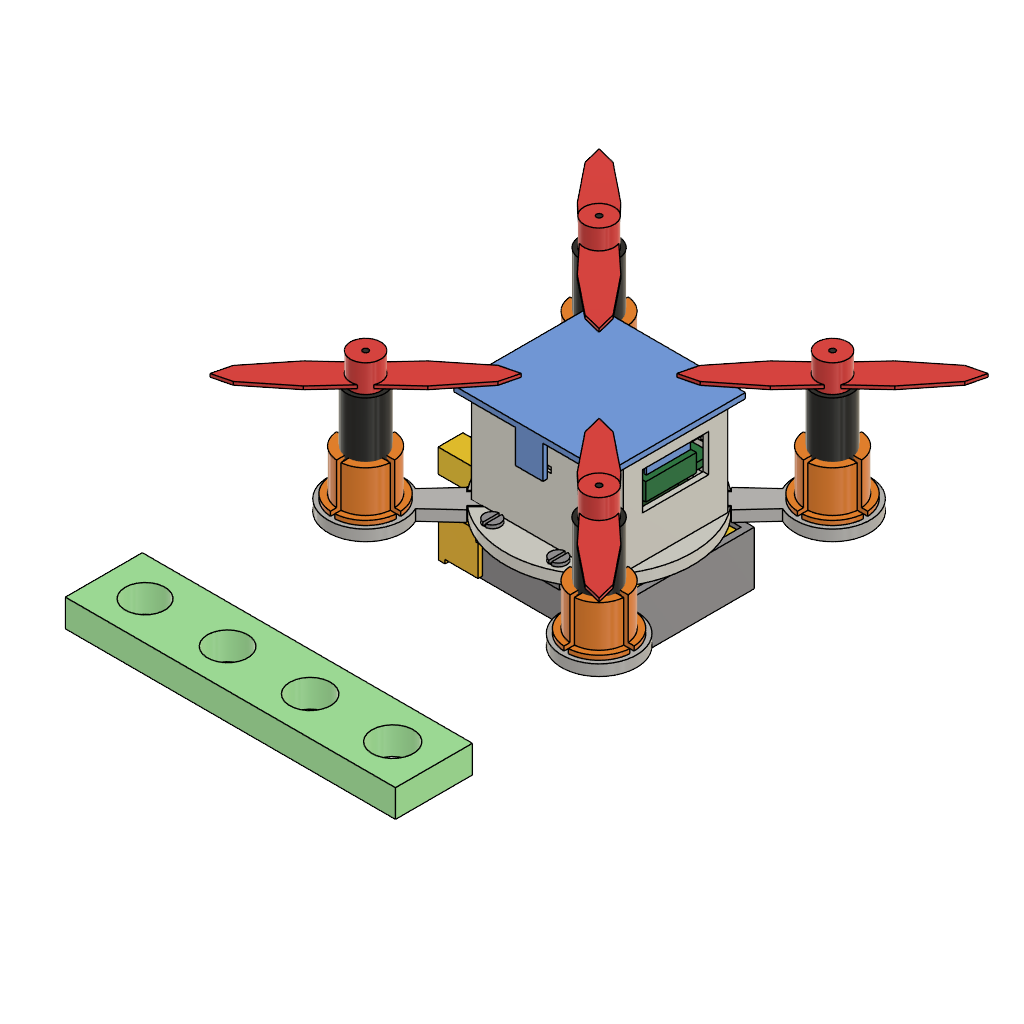
MINI DRONE S3 (Autodesk Fusion 360 design; units mm, degrees)
part number: 2026-10-19-23-11-20-480
part number: 2026-10-19-23-11-20-874
part number: 2026-10-19-23-11-22-508
part number: 2026-10-19-23-11-23-026
part number: 2026-10-19-23-11-23-873
part number: 2026-10-19-23-11-24-034
part number: 2026-10-19-23-11-24-322
part number: 2026-10-19-23-11-25-069
part number: 2026-10-19-23-11-26-284
part number: 2026-10-19-23-11-26-518
part number: 2026-10-19-23-11-26-952
part number: 2026-10-19-23-11-28-014
part number: 2026-10-19-23-11-29-690
part number: 2026-10-19-23-11-29-984
part number: 2026-10-19-23-11-30-548
part number: 2026-10-19-23-11-31-840
part number: 2026-10-19-23-11-33-880
part number: 2026-10-19-23-11-34-265
part number: 2026-10-19-23-11-35-210
part number: 2026-10-19-23-11-38-484
part number: 2026-10-19-23-11-46-425
part number: 2026-10-19-23-11-48-847
part number: 2026-10-19-23-11-50-722
part number: 2026-10-19-23-11-52-088
part number: 2026-10-19-23-11-53-497
part number: 2026-10-19-23-11-56-236
Autodesk Fusion 360 part; units mm, degrees
(part 1 of 2)
sketch "Sketch1" plane through (0, 0, 0) normal (0, 0, 1) x (1, 0, 0) in component "Frame_Core"
  circle A0 centre (0, 0) radius 17
extrude "Extrude1" add sketch "Sketch1" along normal blind 2 makes body 1 in component "Frame_Core"
sketch "Sketch2" plane through (0, 0, 0) normal (0, 0, 1) x (1, 0, 0) in component "Frame_Core"
  line L0 (6.7175, 2.4749) -> (8.8388, 4.5962)
  line L1 (8.8388, 4.5962) -> (4.5962, 8.8388)
  line L2 (4.5962, 8.8388) -> (2.4749, 6.7175)
  line L3 (2.4749, 6.7175) -> (6.7175, 2.4749)
extrude "Extrude2" cut sketch "Sketch2" along normal blind 2.2 from surface at -0.1 bodies 1 in component "Frame_Core"
sketch "Sketch3" plane through (0, 0, 0) normal (0, 0, 1) x (1, 0, 0) in component "Frame_Core"
  line L0 (7.9196, 5.374) -> (14.1421, 11.5966)
  line L1 (14.1421, 11.5966) -> (11.5966, 14.1421)
  line L2 (11.5966, 14.1421) -> (5.374, 7.9196)
  line L3 (5.374, 7.9196) -> (7.9196, 5.374)
extrude "Extrude3" cut sketch "Sketch3" along normal blind 2.2 from surface at -0.1 bodies 1 in component "Frame_Core"
sketch "Sketch4" plane through (0, 0, 0) normal (0, 0, 1) x (1, 0, 0) in component "Frame_Core"
  line L0 (-2.4749, 6.7175) -> (-4.5962, 8.8388)
  line L1 (-4.5962, 8.8388) -> (-8.8388, 4.5962)
  line L2 (-8.8388, 4.5962) -> (-6.7175, 2.4749)
  line L3 (-6.7175, 2.4749) -> (-2.4749, 6.7175)
extrude "Extrude4" cut sketch "Sketch4" along normal blind 2.2 from surface at -0.1 bodies 1 in component "Frame_Core"
sketch "Sketch5" plane through (0, 0, 0) normal (0, 0, 1) x (1, 0, 0) in component "Frame_Core"
  line L0 (-5.374, 7.9196) -> (-11.5966, 14.1421)
  line L1 (-11.5966, 14.1421) -> (-14.1421, 11.5966)
  line L2 (-14.1421, 11.5966) -> (-7.9196, 5.374)
  line L3 (-7.9196, 5.374) -> (-5.374, 7.9196)
extrude "Extrude5" cut sketch "Sketch5" along normal blind 2.2 from surface at -0.1 bodies 1 in component "Frame_Core"
sketch "Sketch6" plane through (0, 0, 0) normal (0, 0, 1) x (1, 0, 0) in component "Frame_Core"
  line L0 (-6.7175, -2.4749) -> (-8.8388, -4.5962)
  line L1 (-8.8388, -4.5962) -> (-4.5962, -8.8388)
  line L2 (-4.5962, -8.8388) -> (-2.4749, -6.7175)
  line L3 (-2.4749, -6.7175) -> (-6.7175, -2.4749)
extrude "Extrude6" cut sketch "Sketch6" along normal blind 2.2 from surface at -0.1 bodies 1 in component "Frame_Core"
sketch "Sketch7" plane through (0, 0, 0) normal (0, 0, 1) x (1, 0, 0) in component "Frame_Core"
  line L0 (-7.9196, -5.374) -> (-14.1421, -11.5966)
  line L1 (-14.1421, -11.5966) -> (-11.5966, -14.1421)
  line L2 (-11.5966, -14.1421) -> (-5.374, -7.9196)
  line L3 (-5.374, -7.9196) -> (-7.9196, -5.374)
extrude "Extrude7" cut sketch "Sketch7" along normal blind 2.2 from surface at -0.1 bodies 1 in component "Frame_Core"
sketch "Sketch8" plane through (0, 0, 0) normal (0, 0, 1) x (1, 0, 0) in component "Frame_Core"
  line L0 (2.4749, -6.7175) -> (4.5962, -8.8388)
  line L1 (4.5962, -8.8388) -> (8.8388, -4.5962)
  line L2 (8.8388, -4.5962) -> (6.7175, -2.4749)
  line L3 (6.7175, -2.4749) -> (2.4749, -6.7175)
extrude "Extrude8" cut sketch "Sketch8" along normal blind 2.2 from surface at -0.1 bodies 1 in component "Frame_Core"
sketch "Sketch9" plane through (0, 0, 0) normal (0, 0, 1) x (1, 0, 0) in component "Frame_Core"
  line L0 (5.374, -7.9196) -> (11.5966, -14.1421)
  line L1 (11.5966, -14.1421) -> (14.1421, -11.5966)
  line L2 (14.1421, -11.5966) -> (7.9196, -5.374)
  line L3 (7.9196, -5.374) -> (5.374, -7.9196)
extrude "Extrude9" cut sketch "Sketch9" along normal blind 2.2 from surface at -0.1 bodies 1 in component "Frame_Core"
sketch "Sketch10" plane through (0, 0, 0) normal (0, 0, 1) x (1, 0, 0) in component "Frame_Core"
  circle A0 centre (-6, -13.4) radius 1.4
extrude "Extrude10" cut sketch "Sketch10" along normal blind 2.2 from surface at -0.1 bodies 1 in component "Frame_Core"
sketch "Sketch11" plane through (0, 0, 0) normal (0, 0, 1) x (1, 0, 0) in component "Frame_Core"
  circle A0 centre (-6, 13.4) radius 1.4
extrude "Extrude11" cut sketch "Sketch11" along normal blind 2.2 from surface at -0.1 bodies 1 in component "Frame_Core"
sketch "Sketch12" plane through (0, 0, 0) normal (0, 0, 1) x (1, 0, 0) in component "Frame_Core"
  circle A0 centre (6, -13.4) radius 1.4
extrude "Extrude12" cut sketch "Sketch12" along normal blind 2.2 from surface at -0.1 bodies 1 in component "Frame_Core"
sketch "Sketch13" plane through (0, 0, 0) normal (0, 0, 1) x (1, 0, 0) in component "Frame_Core"
  circle A0 centre (6, 13.4) radius 1.4
extrude "Extrude13" cut sketch "Sketch13" along normal blind 2.2 from surface at -0.1 bodies 1 in component "Frame_Core"
sketch "Sketch14" plane through (0, 0, 0) normal (0, 0, 1) x (1, 0, 0) in component "Frame_Core"
  line L0 (-11.5, -11.7) -> (11.5, -11.7)
  line L1 (11.5, -11.7) -> (11.5, -9.5)
  line L2 (11.5, -9.5) -> (-11.5, -9.5)
  line L3 (-11.5, -9.5) -> (-11.5, -11.7)
extrude "Extrude14" add sketch "Sketch14" along normal blind 16.4 from surface at 1.9 bodies 1 in component "Frame_Core"
sketch "Sketch15" plane through (0, 0, 0) normal (0, 0, 1) x (1, 0, 0) in component "Frame_Core"
  line L0 (-11.5, 9.5) -> (11.5, 9.5)
  line L1 (11.5, 9.5) -> (11.5, 11.7)
  line L2 (11.5, 11.7) -> (-11.5, 11.7)
  line L3 (-11.5, 11.7) -> (-11.5, 9.5)
extrude "Extrude15" add sketch "Sketch15" along normal blind 16.4 from surface at 1.9 bodies 1 in component "Frame_Core"
sketch "Sketch16" plane through (0, 0, 0) normal (0, 0, 1) x (1, 0, 0) in component "Frame_Core"
  line L0 (12.9, -9.5) -> (13.9, -9.5)
  line L1 (13.9, -9.5) -> (13.9, 9.5)
  line L2 (13.9, 9.5) -> (12.9, 9.5)
  line L3 (12.9, 9.5) -> (12.9, -9.5)
extrude "Extrude16" add sketch "Sketch16" along normal blind 16.4 from surface at 1.9 bodies 1 in component "Frame_Core"
sketch "Sketch17" plane through (0, 0, 0) normal (0, 0, 1) x (1, 0, 0) in component "Frame_Core"
  line L0 (-11.5, -9.6) -> (11.5, -9.6)
  line L1 (11.5, -9.6) -> (11.5, -8)
  line L2 (11.5, -8) -> (-11.5, -8)
  line L3 (-11.5, -8) -> (-11.5, -9.6)
extrude "Extrude17" add sketch "Sketch17" along normal blind 1.3 from surface at 1.9 bodies 1 in component "Frame_Core"
sketch "Sketch18" plane through (0, 0, 0) normal (0, 0, 1) x (1, 0, 0) in component "Frame_Core"
  line L0 (-11.5, -9.6) -> (11.5, -9.6)
  line L1 (11.5, -9.6) -> (11.5, -8)
  line L2 (11.5, -8) -> (-11.5, -8)
  line L3 (-11.5, -8) -> (-11.5, -9.6)
extrude "Extrude18" add sketch "Sketch18" along normal blind 1 from surface at 5.1 bodies 1 in component "Frame_Core"
sketch "Sketch19" plane through (0, 0, 0) normal (0, 0, 1) x (1, 0, 0) in component "Frame_Core"
  line L0 (-11.5, 8) -> (11.5, 8)
  line L1 (11.5, 8) -> (11.5, 9.6)
  line L2 (11.5, 9.6) -> (-11.5, 9.6)
  line L3 (-11.5, 9.6) -> (-11.5, 8)
extrude "Extrude19" add sketch "Sketch19" along normal blind 1.3 from surface at 1.9 bodies 1 in component "Frame_Core"
sketch "Sketch20" plane through (0, 0, 0) normal (0, 0, 1) x (1, 0, 0) in component "Frame_Core"
  line L0 (-11.5, 8) -> (11.5, 8)
  line L1 (11.5, 8) -> (11.5, 9.6)
  line L2 (11.5, 9.6) -> (-11.5, 9.6)
  line L3 (-11.5, 9.6) -> (-11.5, 8)
extrude "Extrude20" add sketch "Sketch20" along normal blind 1 from surface at 5.1 bodies 1 in component "Frame_Core"
sketch "Sketch21" plane through (0, 0, 0) normal (0, 0, 1) x (1, 0, 0) in component "Frame_Core"
  line L0 (-11.5, -9.6) -> (11.5, -9.6)
  line L1 (11.5, -9.6) -> (11.5, -7.9)
  line L2 (11.5, -7.9) -> (-11.5, -7.9)
  line L3 (-11.5, -7.9) -> (-11.5, -9.6)
extrude "Extrude21" add sketch "Sketch21" along normal blind 1.1 from surface at 8.9 bodies 1 in component "Frame_Core"
sketch "Sketch22" plane through (0, 0, 0) normal (0, 0, 1) x (1, 0, 0) in component "Frame_Core"
  line L0 (-11.5, -9.6) -> (11.5, -9.6)
  line L1 (11.5, -9.6) -> (11.5, -7.9)
  line L2 (11.5, -7.9) -> (-11.5, -7.9)
  line L3 (-11.5, -7.9) -> (-11.5, -9.6)
extrude "Extrude22" add sketch "Sketch22" along normal blind 1 from surface at 11.5 bodies 1 in component "Frame_Core"
sketch "Sketch23" plane through (0, 0, 0) normal (0, 0, 1) x (1, 0, 0) in component "Frame_Core"
  line L0 (-11.5, 7.9) -> (11.5, 7.9)
  line L1 (11.5, 7.9) -> (11.5, 9.6)
  line L2 (11.5, 9.6) -> (-11.5, 9.6)
  line L3 (-11.5, 9.6) -> (-11.5, 7.9)
extrude "Extrude23" add sketch "Sketch23" along normal blind 1.1 from surface at 8.9 bodies 1 in component "Frame_Core"
sketch "Sketch24" plane through (0, 0, 0) normal (0, 0, 1) x (1, 0, 0) in component "Frame_Core"
  line L0 (-11.5, 7.9) -> (11.5, 7.9)
  line L1 (11.5, 7.9) -> (11.5, 9.6)
  line L2 (11.5, 9.6) -> (-11.5, 9.6)
  line L3 (-11.5, 9.6) -> (-11.5, 7.9)
extrude "Extrude24" add sketch "Sketch24" along normal blind 1 from surface at 11.5 bodies 1 in component "Frame_Core"
sketch "Sketch25" plane through (0, 0, 0) normal (0, 0, 1) x (1, 0, 0) in component "Frame_Core"
  line L0 (-11.5, -9.6) -> (11.5, -9.6)
  line L1 (11.5, -9.6) -> (11.5, -7)
  line L2 (11.5, -7) -> (-11.5, -7)
  line L3 (-11.5, -7) -> (-11.5, -9.6)
extrude "Extrude25" add sketch "Sketch25" along normal blind 1.1 from surface at 13.4 bodies 1 in component "Frame_Core"
sketch "Sketch26" plane through (0, 0, 0) normal (0, 0, 1) x (1, 0, 0) in component "Frame_Core"
  line L0 (-11.5, -9.6) -> (11.5, -9.6)
  line L1 (11.5, -9.6) -> (11.5, -7)
  line L2 (11.5, -7) -> (-11.5, -7)
  line L3 (-11.5, -7) -> (-11.5, -9.6)
extrude "Extrude26" add sketch "Sketch26" along normal blind 1 from surface at 16.4 bodies 1 in component "Frame_Core"
sketch "Sketch27" plane through (0, 0, 0) normal (0, 0, 1) x (1, 0, 0) in component "Frame_Core"
  line L0 (-11.5, 7) -> (11.5, 7)
  line L1 (11.5, 7) -> (11.5, 9.6)
  line L2 (11.5, 9.6) -> (-11.5, 9.6)
  line L3 (-11.5, 9.6) -> (-11.5, 7)
extrude "Extrude27" add sketch "Sketch27" along normal blind 1.1 from surface at 13.4 bodies 1 in component "Frame_Core"
sketch "Sketch28" plane through (0, 0, 0) normal (0, 0, 1) x (1, 0, 0) in component "Frame_Core"
  line L0 (-11.5, 7) -> (11.5, 7)
  line L1 (11.5, 7) -> (11.5, 9.6)
  line L2 (11.5, 9.6) -> (-11.5, 9.6)
  line L3 (-11.5, 9.6) -> (-11.5, 7)
extrude "Extrude28" add sketch "Sketch28" along normal blind 1 from surface at 16.4 bodies 1 in component "Frame_Core"
sketch "Sketch29" plane through (0, 0, 0) normal (0, 0, 1) x (1, 0, 0) in component "Frame_Core"
  line L0 (-3, -11.8) -> (3, -11.8)
  line L1 (3, -11.8) -> (3, -11.2)
  line L2 (3, -11.2) -> (-3, -11.2)
  line L3 (-3, -11.2) -> (-3, -11.8)
extrude "Extrude29" cut sketch "Sketch29" along normal blind 1 from surface at 13.3 bodies 1 in component "Frame_Core"
sketch "Sketch30" plane through (0, 0, 0) normal (0, 0, 1) x (1, 0, 0) in component "Frame_Core"
  line L0 (-3, 11.2) -> (3, 11.2)
  line L1 (3, 11.2) -> (3, 11.8)
  line L2 (3, 11.8) -> (-3, 11.8)
  line L3 (-3, 11.8) -> (-3, 11.2)
extrude "Extrude30" cut sketch "Sketch30" along normal blind 1 from surface at 13.3 bodies 1 in component "Frame_Core"
sketch "Sketch31" plane through (0, 0, 0) normal (0, 0, 1) x (1, 0, 0) in component "Frame_Core"
  line L0 (12.8, -6) -> (14, -6)
  line L1 (14, -6) -> (14, 6)
  line L2 (14, 6) -> (12.8, 6)
  line L3 (12.8, 6) -> (12.8, -6)
extrude "Extrude31" cut sketch "Sketch31" along normal blind 6.8 from surface at 9.7 bodies 1 in component "Frame_Core"
sketch "Sketch1 (2)" plane through (0, 0, 0) normal (0, 0, 1) x (1, 0, 0) in component "Arm_FR"
  line L0 (6.7175, 2.8284) -> (8.4853, 4.5962)
  line L1 (8.4853, 4.5962) -> (4.5962, 8.4853)
  line L2 (4.5962, 8.4853) -> (2.8284, 6.7175)
  line L3 (2.8284, 6.7175) -> (6.7175, 2.8284)
extrude "Extrude1'" add sketch "Sketch1 (2)" along normal blind 2 separate body makes body 2 in component "Arm_FR"
sketch "Sketch2 (2)" plane through (0, 0, 0) normal (0, 0, 1) x (1, 0, 0) in component "Arm_FR"
  line L0 (7.46, 5.2679) -> (13.3997, 11.2076)
  line L1 (13.3997, 11.2076) -> (11.2076, 13.3997)
  line L2 (11.2076, 13.3997) -> (5.2679, 7.46)
  line L3 (5.2679, 7.46) -> (7.46, 5.2679)
extrude "Extrude2'" add sketch "Sketch2 (2)" along normal blind 2 bodies 2 in component "Arm_FR"
sketch "Sketch3 (2)" plane through (0, 0, 0) normal (0, 0, 1) x (1, 0, 0) in component "Arm_FR"
  line L0 (13.7886, 10.253) -> (22.6274, 19.799)
  line L1 (22.6274, 19.799) -> (19.799, 22.6274)
  line L2 (19.799, 22.6274) -> (10.253, 13.7886)
  line L3 (10.253, 13.7886) -> (13.7886, 10.253)
extrude "Extrude3'" add sketch "Sketch3 (2)" along normal blind 2 bodies 2 in component "Arm_FR"
sketch "Sketch4 (2)" plane through (0, 0, 0) normal (0, 0, 1) x (1, 0, 0) in component "Arm_FR"
  circle A0 centre (21.2132, 21.2132) radius 6.8
extrude "Extrude4'" add sketch "Sketch4 (2)" along normal blind 2 bodies 2 in component "Arm_FR"
sketch "Sketch5 (2)" plane through (0, 0, 0) normal (0, 0, 1) x (1, 0, 0) in component "Arm_FR"
  circle A0 centre (21.2132, 21.2132) radius 5.05
extrude "Extrude5'" cut sketch "Sketch5 (2)" along normal blind 2.2 from surface at -0.1 bodies 2 in component "Arm_FR"
sketch "Sketch6 (2)" plane through (0, 0, 0) normal (0, 0, 1) x (1, 0, 0) in component "Arm_FR"
  line L0 (12.8693, 11.4551) -> (19.0919, 17.6777)
  line L1 (19.0919, 17.6777) -> (17.6777, 19.0919)
  line L2 (17.6777, 19.0919) -> (11.4551, 12.8693)
  line L3 (11.4551, 12.8693) -> (12.8693, 11.4551)
extrude "Extrude6'" cut sketch "Sketch6 (2)" along normal blind 0.9 from surface at -0.1 bodies 2 in component "Arm_FR"
sketch "Sketch7 (2)" plane through (0, 0, 0) normal (0, 0, 1) x (1, 0, 0) in component "Arm_FR"
  line L0 (7.46, 9.5106) -> (8.1671, 10.2177)
  line L1 (8.1671, 10.2177) -> (7.8135, 10.5712)
  line L2 (7.8135, 10.5712) -> (7.1064, 9.8641)
  line L3 (7.1064, 9.8641) -> (7.46, 9.5106)
extrude "Extrude7'" add sketch "Sketch7 (2)" along normal blind 2 bodies 2 in component "Arm_FR"
sketch "Sketch8 (2)" plane through (0, 0, 0) normal (0, 0, 1) x (1, 0, 0) in component "Arm_FR"
  line L0 (9.8641, 7.1064) -> (10.5712, 7.8135)
  line L1 (10.5712, 7.8135) -> (10.2177, 8.1671)
  line L2 (10.2177, 8.1671) -> (9.5106, 7.46)
  line L3 (9.5106, 7.46) -> (9.8641, 7.1064)
extrude "Extrude8'" add sketch "Sketch8 (2)" along normal blind 2 bodies 2 in component "Arm_FR"
sketch "Sketch1 (3)" plane through (0, 0, 0) normal (0, 0, 1) x (1, 0, 0) in component "Pod_FR"
  circle A0 centre (21.2132, 21.2132) radius 4.9
extrude "Extrude1''" add sketch "Sketch1 (3)" along normal blind 11.2 from surface at -0.9 separate body makes body 3 in component "Pod_FR"
sketch "Sketch2 (3)" plane through (0, 0, 0) normal (0, 0, 1) x (1, 0, 0) in component "Pod_FR"
  circle A0 centre (21.2132, 21.2132) radius 6
extrude "Extrude2''" add sketch "Sketch2 (3)" along normal blind 0.8 from surface at 2 bodies 3 in component "Pod_FR"
sketch "Sketch3 (3)" plane through (0, 0, 0) normal (0, 0, 1) x (1, 0, 0) in component "Pod_FR"
  circle A0 centre (21.2132, 21.2132) radius 5.5
extrude "Extrude3''" add sketch "Sketch3 (3)" along normal blind 0.9 from surface at -0.9 bodies 3 in component "Pod_FR"
sketch "Sketch4 (3)" plane through (0, 0, 0) normal (0, 0, 1) x (1, 0, 0) in component "Pod_FR"
  circle A0 centre (21.2132, 21.2132) radius 3.65
extrude "Extrude4''" cut sketch "Sketch4 (3)" along normal blind 10.1 from surface at 0.3 bodies 3 in component "Pod_FR"
sketch "Sketch5 (3)" plane through (0, 0, 0) normal (0, 0, 1) x (1, 0, 0) in component "Pod_FR"
  circle A0 centre (21.2132, 21.2132) radius 3.95
extrude "Extrude5''" add sketch "Sketch5 (3)" along normal blind 0.7 from surface at 9.6 bodies 3 in component "Pod_FR"
sketch "Sketch6 (3)" plane through (0, 0, 0) normal (0, 0, 1) x (1, 0, 0) in component "Pod_FR"
  circle A0 centre (21.2132, 21.2132) radius 3.3
extrude "Extrude6''" cut sketch "Sketch6 (3)" along normal blind 0.9 from surface at 9.5 bodies 3 in component "Pod_FR"
sketch "Sketch7 (3)" plane through (0, 0, 0) normal (0, 0, 1) x (1, 0, 0) in component "Pod_FR"
  circle A0 centre (21.2132, 21.2132) radius 2.2
extrude "Extrude7''" cut sketch "Sketch7 (3)" along normal blind 1.4 from surface at -1 bodies 3 in component "Pod_FR"
sketch "Sketch8 (3)" plane through (0, 0, 0) normal (0, 0, 1) x (1, 0, 0) in component "Pod_FR"
  line L0 (20.8132, 24.1132) -> (21.6132, 24.1132)
  line L1 (21.6132, 24.1132) -> (21.6132, 27.7132)
  line L2 (21.6132, 27.7132) -> (20.8132, 27.7132)
  line L3 (20.8132, 27.7132) -> (20.8132, 24.1132)
extrude "Extrude8''" cut sketch "Sketch8 (3)" along normal blind 11.4 from surface at -1 bodies 3 in component "Pod_FR"
sketch "Sketch9 (2)" plane through (0, 0, 0) normal (0, 0, 1) x (1, 0, 0) in component "Pod_FR"
  line L0 (20.8132, 14.7132) -> (21.6132, 14.7132)
  line L1 (21.6132, 14.7132) -> (21.6132, 18.3132)
  line L2 (21.6132, 18.3132) -> (20.8132, 18.3132)
  line L3 (20.8132, 18.3132) -> (20.8132, 14.7132)
extrude "Extrude9'" cut sketch "Sketch9 (2)" along normal blind 11.4 from surface at -1 bodies 3 in component "Pod_FR"
sketch "Sketch10 (2)" plane through (0, 0, 0) normal (0, 0, 1) x (1, 0, 0) in component "Pod_FR"
  line L0 (24.1132, 20.8132) -> (27.7132, 20.8132)
  line L1 (27.7132, 20.8132) -> (27.7132, 21.6132)
  line L2 (27.7132, 21.6132) -> (24.1132, 21.6132)
  line L3 (24.1132, 21.6132) -> (24.1132, 20.8132)
extrude "Extrude10'" cut sketch "Sketch10 (2)" along normal blind 11.4 from surface at -1 bodies 3 in component "Pod_FR"
sketch "Sketch11 (2)" plane through (0, 0, 0) normal (0, 0, 1) x (1, 0, 0) in component "Pod_FR"
  line L0 (14.7132, 20.8132) -> (18.3132, 20.8132)
  line L1 (18.3132, 20.8132) -> (18.3132, 21.6132)
  line L2 (18.3132, 21.6132) -> (14.7132, 21.6132)
  line L3 (14.7132, 21.6132) -> (14.7132, 20.8132)
extrude "Extrude11'" cut sketch "Sketch11 (2)" along normal blind 11.4 from surface at -1 bodies 3 in component "Pod_FR"
sketch "Sketch12 (2)" plane through (0, 0, 0) normal (0, 0, 1) x (1, 0, 0) in component "Pod_FR"
  line L0 (18.3141, 16.617) -> (20.0111, 18.3141)
  line L1 (20.0111, 18.3141) -> (18.3141, 20.0111)
  line L2 (18.3141, 20.0111) -> (16.617, 18.3141)
  line L3 (16.617, 18.3141) -> (18.3141, 16.617)
extrude "Extrude12'" cut sketch "Sketch12 (2)" along normal blind 2 from surface at -1 bodies 3 in component "Pod_FR"
sketch "Sketch1 (4)" plane through (0, 0, 0) normal (0, 0, 1) x (1, 0, 0) in component "Motor_FR"
  circle A0 centre (21.2132, 21.2132) radius 3.5
extrude "Extrude1'''" add sketch "Sketch1 (4)" along normal blind 20 from surface at 0.3 separate body makes body 4 in component "Motor_FR"
sketch "Sketch2 (4)" plane through (0, 0, 0) normal (0, 0, 1) x (1, 0, 0) in component "Motor_FR"
  circle A0 centre (21.2132, 21.2132) radius 0.5
extrude "Extrude2'''" add sketch "Sketch2 (4)" along normal blind 5.1 from surface at 20.2 bodies 4 in component "Motor_FR"
sketch "Sketch1 (5)" plane through (0, 0, 0) normal (0, 0, 1) x (1, 0, 0) in component "Prop_FR"
  circle A0 centre (21.2132, 21.2132) radius 2.75
extrude "Extrude1''''" add sketch "Sketch1 (5)" along normal blind 5 from surface at 20.3 separate body makes body 5 in component "Prop_FR"
sketch "Sketch2 (5)" plane through (0, 0, 0) normal (0, 0, 1) x (1, 0, 0) in component "Prop_FR"
  line L0 (22.981, 19.4454) -> (28.85, 24.8902)
  line L1 (28.85, 24.8902) -> (34.5068, 31.9612)
  line L2 (34.5068, 31.9612) -> (35.3553, 35.3553)
  line L3 (35.3553, 35.3553) -> (31.9612, 34.5068)
  line L4 (31.9612, 34.5068) -> (24.8902, 28.85)
  line L5 (24.8902, 28.85) -> (19.4454, 22.981)
  line L6 (19.4454, 22.981) -> (13.5765, 17.5362)
  line L7 (13.5765, 17.5362) -> (7.9196, 10.4652)
  line L8 (7.9196, 10.4652) -> (7.0711, 7.0711)
  line L9 (7.0711, 7.0711) -> (10.4652, 7.9196)
  line L10 (10.4652, 7.9196) -> (17.5362, 13.5765)
  line L11 (17.5362, 13.5765) -> (22.981, 19.4454)
extrude "Extrude2''''" add sketch "Sketch2 (5)" along normal blind 0.6 from surface at 21.1 bodies 5 in component "Prop_FR"
sketch "Sketch3 (4)" plane through (0, 0, 0) normal (0, 0, 1) x (1, 0, 0) in component "Prop_FR"
  circle A0 centre (21.2132, 21.2132) radius 0.5
extrude "Extrude3'''" cut sketch "Sketch3 (4)" along normal blind 5.2 from surface at 20.2 bodies 5 in component "Prop_FR"
sketch "Sketch1 (6)" plane through (0, 0, 0) normal (0, 0, 1) x (1, 0, 0) in component "Arm_FL"
  line L0 (-2.8284, 6.7175) -> (-4.5962, 8.4853)
  line L1 (-4.5962, 8.4853) -> (-8.4853, 4.5962)
  line L2 (-8.4853, 4.5962) -> (-6.7175, 2.8284)
  line L3 (-6.7175, 2.8284) -> (-2.8284, 6.7175)
extrude "Extrude1'''''" add sketch "Sketch1 (6)" along normal blind 2 separate body makes body 6 in component "Arm_FL"
sketch "Sketch2 (6)" plane through (0, 0, 0) normal (0, 0, 1) x (1, 0, 0) in component "Arm_FL"
  line L0 (-5.2679, 7.46) -> (-11.2076, 13.3997)
  line L1 (-11.2076, 13.3997) -> (-13.3997, 11.2076)
  line L2 (-13.3997, 11.2076) -> (-7.46, 5.2679)
  line L3 (-7.46, 5.2679) -> (-5.2679, 7.46)
extrude "Extrude2'''''" add sketch "Sketch2 (6)" along normal blind 2 bodies 6 in component "Arm_FL"
sketch "Sketch3 (5)" plane through (0, 0, 0) normal (0, 0, 1) x (1, 0, 0) in component "Arm_FL"
  line L0 (-10.253, 13.7886) -> (-19.799, 22.6274)
  line L1 (-19.799, 22.6274) -> (-22.6274, 19.799)
  line L2 (-22.6274, 19.799) -> (-13.7886, 10.253)
  line L3 (-13.7886, 10.253) -> (-10.253, 13.7886)
extrude "Extrude3''''" add sketch "Sketch3 (5)" along normal blind 2 bodies 6 in component "Arm_FL"
sketch "Sketch4 (4)" plane through (0, 0, 0) normal (0, 0, 1) x (1, 0, 0) in component "Arm_FL"
  circle A0 centre (-21.2132, 21.2132) radius 6.8
extrude "Extrude4'''" add sketch "Sketch4 (4)" along normal blind 2 bodies 6 in component "Arm_FL"
sketch "Sketch5 (4)" plane through (0, 0, 0) normal (0, 0, 1) x (1, 0, 0) in component "Arm_FL"
  circle A0 centre (-21.2132, 21.2132) radius 5.05
extrude "Extrude5'''" cut sketch "Sketch5 (4)" along normal blind 2.2 from surface at -0.1 bodies 6 in component "Arm_FL"
sketch "Sketch6 (4)" plane through (0, 0, 0) normal (0, 0, 1) x (1, 0, 0) in component "Arm_FL"
  line L0 (-11.4551, 12.8693) -> (-17.6777, 19.0919)
  line L1 (-17.6777, 19.0919) -> (-19.0919, 17.6777)
  line L2 (-19.0919, 17.6777) -> (-12.8693, 11.4551)
  line L3 (-12.8693, 11.4551) -> (-11.4551, 12.8693)
extrude "Extrude6'''" cut sketch "Sketch6 (4)" along normal blind 0.9 from surface at -0.1 bodies 6 in component "Arm_FL"
sketch "Sketch7 (4)" plane through (0, 0, 0) normal (0, 0, 1) x (1, 0, 0) in component "Arm_FL"
  line L0 (-9.5106, 7.46) -> (-10.2177, 8.1671)
  line L1 (-10.2177, 8.1671) -> (-10.5712, 7.8135)
  line L2 (-10.5712, 7.8135) -> (-9.8641, 7.1064)
  line L3 (-9.8641, 7.1064) -> (-9.5106, 7.46)
extrude "Extrude7'''" add sketch "Sketch7 (4)" along normal blind 2 bodies 6 in component "Arm_FL"
sketch "Sketch8 (4)" plane through (0, 0, 0) normal (0, 0, 1) x (1, 0, 0) in component "Arm_FL"
  line L0 (-7.1064, 9.8641) -> (-7.8135, 10.5712)
  line L1 (-7.8135, 10.5712) -> (-8.1671, 10.2177)
  line L2 (-8.1671, 10.2177) -> (-7.46, 9.5106)
  line L3 (-7.46, 9.5106) -> (-7.1064, 9.8641)
extrude "Extrude8'''" add sketch "Sketch8 (4)" along normal blind 2 bodies 6 in component "Arm_FL"
sketch "Sketch1 (7)" plane through (0, 0, 0) normal (0, 0, 1) x (1, 0, 0) in component "Pod_FL"
  circle A0 centre (-21.2132, 21.2132) radius 4.9
extrude "Extrude1''''''" add sketch "Sketch1 (7)" along normal blind 11.2 from surface at -0.9 separate body makes body 7 in component "Pod_FL"
sketch "Sketch2 (7)" plane through (0, 0, 0) normal (0, 0, 1) x (1, 0, 0) in component "Pod_FL"
  circle A0 centre (-21.2132, 21.2132) radius 6
extrude "Extrude2''''''" add sketch "Sketch2 (7)" along normal blind 0.8 from surface at 2 bodies 7 in component "Pod_FL"
sketch "Sketch3 (6)" plane through (0, 0, 0) normal (0, 0, 1) x (1, 0, 0) in component "Pod_FL"
  circle A0 centre (-21.2132, 21.2132) radius 5.5
extrude "Extrude3'''''" add sketch "Sketch3 (6)" along normal blind 0.9 from surface at -0.9 bodies 7 in component "Pod_FL"
sketch "Sketch4 (5)" plane through (0, 0, 0) normal (0, 0, 1) x (1, 0, 0) in component "Pod_FL"
  circle A0 centre (-21.2132, 21.2132) radius 3.65
extrude "Extrude4''''" cut sketch "Sketch4 (5)" along normal blind 10.1 from surface at 0.3 bodies 7 in component "Pod_FL"
sketch "Sketch5 (5)" plane through (0, 0, 0) normal (0, 0, 1) x (1, 0, 0) in component "Pod_FL"
  circle A0 centre (-21.2132, 21.2132) radius 3.95
extrude "Extrude5''''" add sketch "Sketch5 (5)" along normal blind 0.7 from surface at 9.6 bodies 7 in component "Pod_FL"
sketch "Sketch6 (5)" plane through (0, 0, 0) normal (0, 0, 1) x (1, 0, 0) in component "Pod_FL"
  circle A0 centre (-21.2132, 21.2132) radius 3.3
extrude "Extrude6''''" cut sketch "Sketch6 (5)" along normal blind 0.9 from surface at 9.5 bodies 7 in component "Pod_FL"
sketch "Sketch7 (5)" plane through (0, 0, 0) normal (0, 0, 1) x (1, 0, 0) in component "Pod_FL"
  circle A0 centre (-21.2132, 21.2132) radius 2.2
extrude "Extrude7''''" cut sketch "Sketch7 (5)" along normal blind 1.4 from surface at -1 bodies 7 in component "Pod_FL"
sketch "Sketch8 (5)" plane through (0, 0, 0) normal (0, 0, 1) x (1, 0, 0) in component "Pod_FL"
  line L0 (-21.6132, 24.1132) -> (-20.8132, 24.1132)
  line L1 (-20.8132, 24.1132) -> (-20.8132, 27.7132)
  line L2 (-20.8132, 27.7132) -> (-21.6132, 27.7132)
  line L3 (-21.6132, 27.7132) -> (-21.6132, 24.1132)
extrude "Extrude8''''" cut sketch "Sketch8 (5)" along normal blind 11.4 from surface at -1 bodies 7 in component "Pod_FL"
sketch "Sketch9 (3)" plane through (0, 0, 0) normal (0, 0, 1) x (1, 0, 0) in component "Pod_FL"
  line L0 (-21.6132, 14.7132) -> (-20.8132, 14.7132)
  line L1 (-20.8132, 14.7132) -> (-20.8132, 18.3132)
  line L2 (-20.8132, 18.3132) -> (-21.6132, 18.3132)
  line L3 (-21.6132, 18.3132) -> (-21.6132, 14.7132)
extrude "Extrude9''" cut sketch "Sketch9 (3)" along normal blind 11.4 from surface at -1 bodies 7 in component "Pod_FL"
sketch "Sketch10 (3)" plane through (0, 0, 0) normal (0, 0, 1) x (1, 0, 0) in component "Pod_FL"
  line L0 (-18.3132, 20.8132) -> (-14.7132, 20.8132)
  line L1 (-14.7132, 20.8132) -> (-14.7132, 21.6132)
  line L2 (-14.7132, 21.6132) -> (-18.3132, 21.6132)
  line L3 (-18.3132, 21.6132) -> (-18.3132, 20.8132)
extrude "Extrude10''" cut sketch "Sketch10 (3)" along normal blind 11.4 from surface at -1 bodies 7 in component "Pod_FL"
sketch "Sketch11 (3)" plane through (0, 0, 0) normal (0, 0, 1) x (1, 0, 0) in component "Pod_FL"
  line L0 (-27.7132, 20.8132) -> (-24.1132, 20.8132)
  line L1 (-24.1132, 20.8132) -> (-24.1132, 21.6132)
  line L2 (-24.1132, 21.6132) -> (-27.7132, 21.6132)
  line L3 (-27.7132, 21.6132) -> (-27.7132, 20.8132)
extrude "Extrude11''" cut sketch "Sketch11 (3)" along normal blind 11.4 from surface at -1 bodies 7 in component "Pod_FL"
sketch "Sketch12 (3)" plane through (0, 0, 0) normal (0, 0, 1) x (1, 0, 0) in component "Pod_FL"
  line L0 (-16.617, 18.3141) -> (-18.3141, 20.0111)
  line L1 (-18.3141, 20.0111) -> (-20.0111, 18.3141)
  line L2 (-20.0111, 18.3141) -> (-18.3141, 16.617)
  line L3 (-18.3141, 16.617) -> (-16.617, 18.3141)
extrude "Extrude12''" cut sketch "Sketch12 (3)" along normal blind 2 from surface at -1 bodies 7 in component "Pod_FL"
sketch "Sketch1 (8)" plane through (0, 0, 0) normal (0, 0, 1) x (1, 0, 0) in component "Motor_FL"
  circle A0 centre (-21.2132, 21.2132) radius 3.5
extrude "Extrude1'''''''" add sketch "Sketch1 (8)" along normal blind 20 from surface at 0.3 separate body makes body 8 in component "Motor_FL"
sketch "Sketch2 (8)" plane through (0, 0, 0) normal (0, 0, 1) x (1, 0, 0) in component "Motor_FL"
  circle A0 centre (-21.2132, 21.2132) radius 0.5
extrude "Extrude2'''''''" add sketch "Sketch2 (8)" along normal blind 5.1 from surface at 20.2 bodies 8 in component "Motor_FL"
sketch "Sketch1 (9)" plane through (0, 0, 0) normal (0, 0, 1) x (1, 0, 0) in component "Prop_FL"
  circle A0 centre (-21.2132, 21.2132) radius 2.75
extrude "Extrude1''''''''" add sketch "Sketch1 (9)" along normal blind 5 from surface at 20.3 separate body makes body 9 in component "Prop_FL"
sketch "Sketch2 (9)" plane through (0, 0, 0) normal (0, 0, 1) x (1, 0, 0) in component "Prop_FL"
  line L0 (-19.4454, 22.981) -> (-24.8902, 28.85)
  line L1 (-24.8902, 28.85) -> (-31.9612, 34.5068)
  line L2 (-31.9612, 34.5068) -> (-35.3553, 35.3553)
  line L3 (-35.3553, 35.3553) -> (-34.5068, 31.9612)
  line L4 (-34.5068, 31.9612) -> (-28.85, 24.8902)
  line L5 (-28.85, 24.8902) -> (-22.981, 19.4454)
  line L6 (-22.981, 19.4454) -> (-17.5362, 13.5765)
  line L7 (-17.5362, 13.5765) -> (-10.4652, 7.9196)
  line L8 (-10.4652, 7.9196) -> (-7.0711, 7.0711)
  line L9 (-7.0711, 7.0711) -> (-7.9196, 10.4652)
  line L10 (-7.9196, 10.4652) -> (-13.5765, 17.5362)
  line L11 (-13.5765, 17.5362) -> (-19.4454, 22.981)
extrude "Extrude2''''''''" add sketch "Sketch2 (9)" along normal blind 0.6 from surface at 21.1 bodies 9 in component "Prop_FL"
sketch "Sketch3 (7)" plane through (0, 0, 0) normal (0, 0, 1) x (1, 0, 0) in component "Prop_FL"
  circle A0 centre (-21.2132, 21.2132) radius 0.5
extrude "Extrude3''''''" cut sketch "Sketch3 (7)" along normal blind 5.2 from surface at 20.2 bodies 9 in component "Prop_FL"
sketch "Sketch1 (10)" plane through (0, 0, 0) normal (0, 0, 1) x (1, 0, 0) in component "Arm_RL"
  line L0 (-6.7175, -2.8284) -> (-8.4853, -4.5962)
  line L1 (-8.4853, -4.5962) -> (-4.5962, -8.4853)
  line L2 (-4.5962, -8.4853) -> (-2.8284, -6.7175)
  line L3 (-2.8284, -6.7175) -> (-6.7175, -2.8284)
extrude "Extrude1'''''''''" add sketch "Sketch1 (10)" along normal blind 2 separate body makes body 10 in component "Arm_RL"
sketch "Sketch2 (10)" plane through (0, 0, 0) normal (0, 0, 1) x (1, 0, 0) in component "Arm_RL"
  line L0 (-7.46, -5.2679) -> (-13.3997, -11.2076)
  line L1 (-13.3997, -11.2076) -> (-11.2076, -13.3997)
  line L2 (-11.2076, -13.3997) -> (-5.2679, -7.46)
  line L3 (-5.2679, -7.46) -> (-7.46, -5.2679)
extrude "Extrude2'''''''''" add sketch "Sketch2 (10)" along normal blind 2 bodies 10 in component "Arm_RL"
sketch "Sketch3 (8)" plane through (0, 0, 0) normal (0, 0, 1) x (1, 0, 0) in component "Arm_RL"
  line L0 (-13.7886, -10.253) -> (-22.6274, -19.799)
  line L1 (-22.6274, -19.799) -> (-19.799, -22.6274)
  line L2 (-19.799, -22.6274) -> (-10.253, -13.7886)
  line L3 (-10.253, -13.7886) -> (-13.7886, -10.253)
extrude "Extrude3'''''''" add sketch "Sketch3 (8)" along normal blind 2 bodies 10 in component "Arm_RL"
sketch "Sketch4 (6)" plane through (0, 0, 0) normal (0, 0, 1) x (1, 0, 0) in component "Arm_RL"
  circle A0 centre (-21.2132, -21.2132) radius 6.8
extrude "Extrude4'''''" add sketch "Sketch4 (6)" along normal blind 2 bodies 10 in component "Arm_RL"
sketch "Sketch5 (6)" plane through (0, 0, 0) normal (0, 0, 1) x (1, 0, 0) in component "Arm_RL"
  circle A0 centre (-21.2132, -21.2132) radius 5.05
extrude "Extrude5'''''" cut sketch "Sketch5 (6)" along normal blind 2.2 from surface at -0.1 bodies 10 in component "Arm_RL"
sketch "Sketch6 (6)" plane through (0, 0, 0) normal (0, 0, 1) x (1, 0, 0) in component "Arm_RL"
  line L0 (-12.8693, -11.4551) -> (-19.0919, -17.6777)
  line L1 (-19.0919, -17.6777) -> (-17.6777, -19.0919)
  line L2 (-17.6777, -19.0919) -> (-11.4551, -12.8693)
  line L3 (-11.4551, -12.8693) -> (-12.8693, -11.4551)
extrude "Extrude6'''''" cut sketch "Sketch6 (6)" along normal blind 0.9 from surface at -0.1 bodies 10 in component "Arm_RL"
sketch "Sketch7 (6)" plane through (0, 0, 0) normal (0, 0, 1) x (1, 0, 0) in component "Arm_RL"
  line L0 (-7.46, -9.5106) -> (-8.1671, -10.2177)
  line L1 (-8.1671, -10.2177) -> (-7.8135, -10.5712)
  line L2 (-7.8135, -10.5712) -> (-7.1064, -9.8641)
  line L3 (-7.1064, -9.8641) -> (-7.46, -9.5106)
extrude "Extrude7'''''" add sketch "Sketch7 (6)" along normal blind 2 bodies 10 in component "Arm_RL"
sketch "Sketch8 (6)" plane through (0, 0, 0) normal (0, 0, 1) x (1, 0, 0) in component "Arm_RL"
  line L0 (-9.8641, -7.1064) -> (-10.5712, -7.8135)
  line L1 (-10.5712, -7.8135) -> (-10.2177, -8.1671)
  line L2 (-10.2177, -8.1671) -> (-9.5106, -7.46)
  line L3 (-9.5106, -7.46) -> (-9.8641, -7.1064)
extrude "Extrude8'''''" add sketch "Sketch8 (6)" along normal blind 2 bodies 10 in component "Arm_RL"
sketch "Sketch1 (11)" plane through (0, 0, 0) normal (0, 0, 1) x (1, 0, 0) in component "Pod_RL"
  circle A0 centre (-21.2132, -21.2132) radius 4.9
extrude "Extrude1''''''''''" add sketch "Sketch1 (11)" along normal blind 11.2 from surface at -0.9 separate body makes body 11 in component "Pod_RL"
sketch "Sketch2 (11)" plane through (0, 0, 0) normal (0, 0, 1) x (1, 0, 0) in component "Pod_RL"
  circle A0 centre (-21.2132, -21.2132) radius 6
extrude "Extrude2''''''''''" add sketch "Sketch2 (11)" along normal blind 0.8 from surface at 2 bodies 11 in component "Pod_RL"
sketch "Sketch3 (9)" plane through (0, 0, 0) normal (0, 0, 1) x (1, 0, 0) in component "Pod_RL"
  circle A0 centre (-21.2132, -21.2132) radius 5.5
extrude "Extrude3''''''''" add sketch "Sketch3 (9)" along normal blind 0.9 from surface at -0.9 bodies 11 in component "Pod_RL"
sketch "Sketch4 (7)" plane through (0, 0, 0) normal (0, 0, 1) x (1, 0, 0) in component "Pod_RL"
  circle A0 centre (-21.2132, -21.2132) radius 3.65
extrude "Extrude4''''''" cut sketch "Sketch4 (7)" along normal blind 10.1 from surface at 0.3 bodies 11 in component "Pod_RL"
sketch "Sketch5 (7)" plane through (0, 0, 0) normal (0, 0, 1) x (1, 0, 0) in component "Pod_RL"
  circle A0 centre (-21.2132, -21.2132) radius 3.95
extrude "Extrude5''''''" add sketch "Sketch5 (7)" along normal blind 0.7 from surface at 9.6 bodies 11 in component "Pod_RL"
sketch "Sketch6 (7)" plane through (0, 0, 0) normal (0, 0, 1) x (1, 0, 0) in component "Pod_RL"
  circle A0 centre (-21.2132, -21.2132) radius 3.3
extrude "Extrude6''''''" cut sketch "Sketch6 (7)" along normal blind 0.9 from surface at 9.5 bodies 11 in component "Pod_RL"
sketch "Sketch7 (7)" plane through (0, 0, 0) normal (0, 0, 1) x (1, 0, 0) in component "Pod_RL"
  circle A0 centre (-21.2132, -21.2132) radius 2.2
extrude "Extrude7''''''" cut sketch "Sketch7 (7)" along normal blind 1.4 from surface at -1 bodies 11 in component "Pod_RL"
sketch "Sketch8 (7)" plane through (0, 0, 0) normal (0, 0, 1) x (1, 0, 0) in component "Pod_RL"
  line L0 (-21.6132, -18.3132) -> (-20.8132, -18.3132)
  line L1 (-20.8132, -18.3132) -> (-20.8132, -14.7132)
  line L2 (-20.8132, -14.7132) -> (-21.6132, -14.7132)
  line L3 (-21.6132, -14.7132) -> (-21.6132, -18.3132)
extrude "Extrude8''''''" cut sketch "Sketch8 (7)" along normal blind 11.4 from surface at -1 bodies 11 in component "Pod_RL"
sketch "Sketch9 (4)" plane through (0, 0, 0) normal (0, 0, 1) x (1, 0, 0) in component "Pod_RL"
  line L0 (-21.6132, -27.7132) -> (-20.8132, -27.7132)
  line L1 (-20.8132, -27.7132) -> (-20.8132, -24.1132)
  line L2 (-20.8132, -24.1132) -> (-21.6132, -24.1132)
  line L3 (-21.6132, -24.1132) -> (-21.6132, -27.7132)
extrude "Extrude9'''" cut sketch "Sketch9 (4)" along normal blind 11.4 from surface at -1 bodies 11 in component "Pod_RL"
sketch "Sketch10 (4)" plane through (0, 0, 0) normal (0, 0, 1) x (1, 0, 0) in component "Pod_RL"
  line L0 (-18.3132, -21.6132) -> (-14.7132, -21.6132)
  line L1 (-14.7132, -21.6132) -> (-14.7132, -20.8132)
  line L2 (-14.7132, -20.8132) -> (-18.3132, -20.8132)
  line L3 (-18.3132, -20.8132) -> (-18.3132, -21.6132)
extrude "Extrude10'''" cut sketch "Sketch10 (4)" along normal blind 11.4 from surface at -1 bodies 11 in component "Pod_RL"
sketch "Sketch11 (4)" plane through (0, 0, 0) normal (0, 0, 1) x (1, 0, 0) in component "Pod_RL"
  line L0 (-27.7132, -21.6132) -> (-24.1132, -21.6132)
  line L1 (-24.1132, -21.6132) -> (-24.1132, -20.8132)
  line L2 (-24.1132, -20.8132) -> (-27.7132, -20.8132)
  line L3 (-27.7132, -20.8132) -> (-27.7132, -21.6132)
extrude "Extrude11'''" cut sketch "Sketch11 (4)" along normal blind 11.4 from surface at -1 bodies 11 in component "Pod_RL"
sketch "Sketch12 (4)" plane through (0, 0, 0) normal (0, 0, 1) x (1, 0, 0) in component "Pod_RL"
  line L0 (-18.3141, -16.617) -> (-20.0111, -18.3141)
  line L1 (-20.0111, -18.3141) -> (-18.3141, -20.0111)
  line L2 (-18.3141, -20.0111) -> (-16.617, -18.3141)
  line L3 (-16.617, -18.3141) -> (-18.3141, -16.617)
extrude "Extrude12'''" cut sketch "Sketch12 (4)" along normal blind 2 from surface at -1 bodies 11 in component "Pod_RL"
sketch "Sketch1 (12)" plane through (0, 0, 0) normal (0, 0, 1) x (1, 0, 0) in component "Motor_RL"
  circle A0 centre (-21.2132, -21.2132) radius 3.5
extrude "Extrude1'''''''''''" add sketch "Sketch1 (12)" along normal blind 20 from surface at 0.3 separate body makes body 12 in component "Motor_RL"
sketch "Sketch2 (12)" plane through (0, 0, 0) normal (0, 0, 1) x (1, 0, 0) in component "Motor_RL"
  circle A0 centre (-21.2132, -21.2132) radius 0.5
extrude "Extrude2'''''''''''" add sketch "Sketch2 (12)" along normal blind 5.1 from surface at 20.2 bodies 12 in component "Motor_RL"
sketch "Sketch1 (13)" plane through (0, 0, 0) normal (0, 0, 1) x (1, 0, 0) in component "Prop_RL"
  circle A0 centre (-21.2132, -21.2132) radius 2.75
extrude "Extrude1''''''''''''" add sketch "Sketch1 (13)" along normal blind 5 from surface at 20.3 separate body makes body 13 in component "Prop_RL"
sketch "Sketch2 (13)" plane through (0, 0, 0) normal (0, 0, 1) x (1, 0, 0) in component "Prop_RL"
  line L0 (-22.981, -19.4454) -> (-28.85, -24.8902)
  line L1 (-28.85, -24.8902) -> (-34.5068, -31.9612)
  line L2 (-34.5068, -31.9612) -> (-35.3553, -35.3553)
  line L3 (-35.3553, -35.3553) -> (-31.9612, -34.5068)
  line L4 (-31.9612, -34.5068) -> (-24.8902, -28.85)
  line L5 (-24.8902, -28.85) -> (-19.4454, -22.981)
  line L6 (-19.4454, -22.981) -> (-13.5765, -17.5362)
  line L7 (-13.5765, -17.5362) -> (-7.9196, -10.4652)
  line L8 (-7.9196, -10.4652) -> (-7.0711, -7.0711)
  line L9 (-7.0711, -7.0711) -> (-10.4652, -7.9196)
  line L10 (-10.4652, -7.9196) -> (-17.5362, -13.5765)
  line L11 (-17.5362, -13.5765) -> (-22.981, -19.4454)
extrude "Extrude2''''''''''''" add sketch "Sketch2 (13)" along normal blind 0.6 from surface at 21.1 bodies 13 in component "Prop_RL"
sketch "Sketch3 (10)" plane through (0, 0, 0) normal (0, 0, 1) x (1, 0, 0) in component "Prop_RL"
  circle A0 centre (-21.2132, -21.2132) radius 0.5
extrude "Extrude3'''''''''" cut sketch "Sketch3 (10)" along normal blind 5.2 from surface at 20.2 bodies 13 in component "Prop_RL"
sketch "Sketch1 (14)" plane through (0, 0, 0) normal (0, 0, 1) x (1, 0, 0) in component "Arm_RR"
  line L0 (2.8284, -6.7175) -> (4.5962, -8.4853)
  line L1 (4.5962, -8.4853) -> (8.4853, -4.5962)
  line L2 (8.4853, -4.5962) -> (6.7175, -2.8284)
  line L3 (6.7175, -2.8284) -> (2.8284, -6.7175)
extrude "Extrude1'''''''''''''" add sketch "Sketch1 (14)" along normal blind 2 separate body makes body 14 in component "Arm_RR"
sketch "Sketch2 (14)" plane through (0, 0, 0) normal (0, 0, 1) x (1, 0, 0) in component "Arm_RR"
  line L0 (5.2679, -7.46) -> (11.2076, -13.3997)
  line L1 (11.2076, -13.3997) -> (13.3997, -11.2076)
  line L2 (13.3997, -11.2076) -> (7.46, -5.2679)
  line L3 (7.46, -5.2679) -> (5.2679, -7.46)
extrude "Extrude2'''''''''''''" add sketch "Sketch2 (14)" along normal blind 2 bodies 14 in component "Arm_RR"
sketch "Sketch3 (11)" plane through (0, 0, 0) normal (0, 0, 1) x (1, 0, 0) in component "Arm_RR"
  line L0 (10.253, -13.7886) -> (19.799, -22.6274)
  line L1 (19.799, -22.6274) -> (22.6274, -19.799)
  line L2 (22.6274, -19.799) -> (13.7886, -10.253)
  line L3 (13.7886, -10.253) -> (10.253, -13.7886)
extrude "Extrude3''''''''''" add sketch "Sketch3 (11)" along normal blind 2 bodies 14 in component "Arm_RR"
sketch "Sketch4 (8)" plane through (0, 0, 0) normal (0, 0, 1) x (1, 0, 0) in component "Arm_RR"
  circle A0 centre (21.2132, -21.2132) radius 6.8
extrude "Extrude4'''''''" add sketch "Sketch4 (8)" along normal blind 2 bodies 14 in component "Arm_RR"
sketch "Sketch5 (8)" plane through (0, 0, 0) normal (0, 0, 1) x (1, 0, 0) in component "Arm_RR"
  circle A0 centre (21.2132, -21.2132) radius 5.05
extrude "Extrude5'''''''" cut sketch "Sketch5 (8)" along normal blind 2.2 from surface at -0.1 bodies 14 in component "Arm_RR"
sketch "Sketch6 (8)" plane through (0, 0, 0) normal (0, 0, 1) x (1, 0, 0) in component "Arm_RR"
  line L0 (11.4551, -12.8693) -> (17.6777, -19.0919)
  line L1 (17.6777, -19.0919) -> (19.0919, -17.6777)
  line L2 (19.0919, -17.6777) -> (12.8693, -11.4551)
  line L3 (12.8693, -11.4551) -> (11.4551, -12.8693)
extrude "Extrude6'''''''" cut sketch "Sketch6 (8)" along normal blind 0.9 from surface at -0.1 bodies 14 in component "Arm_RR"
sketch "Sketch7 (8)" plane through (0, 0, 0) normal (0, 0, 1) x (1, 0, 0) in component "Arm_RR"
  line L0 (9.5106, -7.46) -> (10.2177, -8.1671)
  line L1 (10.2177, -8.1671) -> (10.5712, -7.8135)
  line L2 (10.5712, -7.8135) -> (9.8641, -7.1064)
  line L3 (9.8641, -7.1064) -> (9.5106, -7.46)
extrude "Extrude7'''''''" add sketch "Sketch7 (8)" along normal blind 2 bodies 14 in component "Arm_RR"
sketch "Sketch8 (8)" plane through (0, 0, 0) normal (0, 0, 1) x (1, 0, 0) in component "Arm_RR"
  line L0 (7.1064, -9.8641) -> (7.8135, -10.5712)
  line L1 (7.8135, -10.5712) -> (8.1671, -10.2177)
  line L2 (8.1671, -10.2177) -> (7.46, -9.5106)
  line L3 (7.46, -9.5106) -> (7.1064, -9.8641)
extrude "Extrude8'''''''" add sketch "Sketch8 (8)" along normal blind 2 bodies 14 in component "Arm_RR"
sketch "Sketch1 (15)" plane through (0, 0, 0) normal (0, 0, 1) x (1, 0, 0) in component "Pod_RR"
  circle A0 centre (21.2132, -21.2132) radius 4.9
extrude "Extrude1''''''''''''''" add sketch "Sketch1 (15)" along normal blind 11.2 from surface at -0.9 separate body makes body 15 in component "Pod_RR"
sketch "Sketch2 (15)" plane through (0, 0, 0) normal (0, 0, 1) x (1, 0, 0) in component "Pod_RR"
  circle A0 centre (21.2132, -21.2132) radius 6
extrude "Extrude2''''''''''''''" add sketch "Sketch2 (15)" along normal blind 0.8 from surface at 2 bodies 15 in component "Pod_RR"
sketch "Sketch3 (12)" plane through (0, 0, 0) normal (0, 0, 1) x (1, 0, 0) in component "Pod_RR"
  circle A0 centre (21.2132, -21.2132) radius 5.5
extrude "Extrude3'''''''''''" add sketch "Sketch3 (12)" along normal blind 0.9 from surface at -0.9 bodies 15 in component "Pod_RR"
sketch "Sketch4 (9)" plane through (0, 0, 0) normal (0, 0, 1) x (1, 0, 0) in component "Pod_RR"
  circle A0 centre (21.2132, -21.2132) radius 3.65
extrude "Extrude4''''''''" cut sketch "Sketch4 (9)" along normal blind 10.1 from surface at 0.3 bodies 15 in component "Pod_RR"
sketch "Sketch5 (9)" plane through (0, 0, 0) normal (0, 0, 1) x (1, 0, 0) in component "Pod_RR"
  circle A0 centre (21.2132, -21.2132) radius 3.95
extrude "Extrude5''''''''" add sketch "Sketch5 (9)" along normal blind 0.7 from surface at 9.6 bodies 15 in component "Pod_RR"
sketch "Sketch6 (9)" plane through (0, 0, 0) normal (0, 0, 1) x (1, 0, 0) in component "Pod_RR"
  circle A0 centre (21.2132, -21.2132) radius 3.3
extrude "Extrude6''''''''" cut sketch "Sketch6 (9)" along normal blind 0.9 from surface at 9.5 bodies 15 in component "Pod_RR"
sketch "Sketch7 (9)" plane through (0, 0, 0) normal (0, 0, 1) x (1, 0, 0) in component "Pod_RR"
  circle A0 centre (21.2132, -21.2132) radius 2.2
extrude "Extrude7''''''''" cut sketch "Sketch7 (9)" along normal blind 1.4 from surface at -1 bodies 15 in component "Pod_RR"
sketch "Sketch8 (9)" plane through (0, 0, 0) normal (0, 0, 1) x (1, 0, 0) in component "Pod_RR"
  line L0 (20.8132, -18.3132) -> (21.6132, -18.3132)
  line L1 (21.6132, -18.3132) -> (21.6132, -14.7132)
  line L2 (21.6132, -14.7132) -> (20.8132, -14.7132)
  line L3 (20.8132, -14.7132) -> (20.8132, -18.3132)
extrude "Extrude8''''''''" cut sketch "Sketch8 (9)" along normal blind 11.4 from surface at -1 bodies 15 in component "Pod_RR"
sketch "Sketch9 (5)" plane through (0, 0, 0) normal (0, 0, 1) x (1, 0, 0) in component "Pod_RR"
  line L0 (20.8132, -27.7132) -> (21.6132, -27.7132)
  line L1 (21.6132, -27.7132) -> (21.6132, -24.1132)
  line L2 (21.6132, -24.1132) -> (20.8132, -24.1132)
  line L3 (20.8132, -24.1132) -> (20.8132, -27.7132)
extrude "Extrude9''''" cut sketch "Sketch9 (5)" along normal blind 11.4 from surface at -1 bodies 15 in component "Pod_RR"
sketch "Sketch10 (5)" plane through (0, 0, 0) normal (0, 0, 1) x (1, 0, 0) in component "Pod_RR"
  line L0 (24.1132, -21.6132) -> (27.7132, -21.6132)
  line L1 (27.7132, -21.6132) -> (27.7132, -20.8132)
  line L2 (27.7132, -20.8132) -> (24.1132, -20.8132)
  line L3 (24.1132, -20.8132) -> (24.1132, -21.6132)
extrude "Extrude10''''" cut sketch "Sketch10 (5)" along normal blind 11.4 from surface at -1 bodies 15 in component "Pod_RR"
sketch "Sketch11 (5)" plane through (0, 0, 0) normal (0, 0, 1) x (1, 0, 0) in component "Pod_RR"
  line L0 (14.7132, -21.6132) -> (18.3132, -21.6132)
  line L1 (18.3132, -21.6132) -> (18.3132, -20.8132)
  line L2 (18.3132, -20.8132) -> (14.7132, -20.8132)
  line L3 (14.7132, -20.8132) -> (14.7132, -21.6132)
extrude "Extrude11''''" cut sketch "Sketch11 (5)" along normal blind 11.4 from surface at -1 bodies 15 in component "Pod_RR"
sketch "Sketch12 (5)" plane through (0, 0, 0) normal (0, 0, 1) x (1, 0, 0) in component "Pod_RR"
  line L0 (16.617, -18.3141) -> (18.3141, -20.0111)
  line L1 (18.3141, -20.0111) -> (20.0111, -18.3141)
  line L2 (20.0111, -18.3141) -> (18.3141, -16.617)
  line L3 (18.3141, -16.617) -> (16.617, -18.3141)
extrude "Extrude12''''" cut sketch "Sketch12 (5)" along normal blind 2 from surface at -1 bodies 15 in component "Pod_RR"
sketch "Sketch1 (16)" plane through (0, 0, 0) normal (0, 0, 1) x (1, 0, 0) in component "Motor_RR"
  circle A0 centre (21.2132, -21.2132) radius 3.5
extrude "Extrude1'''''''''''''''" add sketch "Sketch1 (16)" along normal blind 20 from surface at 0.3 separate body makes body 16 in component "Motor_RR"
sketch "Sketch2 (16)" plane through (0, 0, 0) normal (0, 0, 1) x (1, 0, 0) in component "Motor_RR"
  circle A0 centre (21.2132, -21.2132) radius 0.5
extrude "Extrude2'''''''''''''''" add sketch "Sketch2 (16)" along normal blind 5.1 from surface at 20.2 bodies 16 in component "Motor_RR"
sketch "Sketch1 (17)" plane through (0, 0, 0) normal (0, 0, 1) x (1, 0, 0) in component "Prop_RR"
  circle A0 centre (21.2132, -21.2132) radius 2.75
extrude "Extrude1''''''''''''''''" add sketch "Sketch1 (17)" along normal blind 5 from surface at 20.3 separate body makes body 17 in component "Prop_RR"
sketch "Sketch2 (17)" plane through (0, 0, 0) normal (0, 0, 1) x (1, 0, 0) in component "Prop_RR"
  line L0 (19.4454, -22.981) -> (24.8902, -28.85)
  line L1 (24.8902, -28.85) -> (31.9612, -34.5068)
  line L2 (31.9612, -34.5068) -> (35.3553, -35.3553)
  line L3 (35.3553, -35.3553) -> (34.5068, -31.9612)
  line L4 (34.5068, -31.9612) -> (28.85, -24.8902)
  line L5 (28.85, -24.8902) -> (22.981, -19.4454)
  line L6 (22.981, -19.4454) -> (17.5362, -13.5765)
  line L7 (17.5362, -13.5765) -> (10.4652, -7.9196)
  line L8 (10.4652, -7.9196) -> (7.0711, -7.0711)
  line L9 (7.0711, -7.0711) -> (7.9196, -10.4652)
  line L10 (7.9196, -10.4652) -> (13.5765, -17.5362)
  line L11 (13.5765, -17.5362) -> (19.4454, -22.981)
extrude "Extrude2''''''''''''''''" add sketch "Sketch2 (17)" along normal blind 0.6 from surface at 21.1 bodies 17 in component "Prop_RR"
sketch "Sketch3 (13)" plane through (0, 0, 0) normal (0, 0, 1) x (1, 0, 0) in component "Prop_RR"
  circle A0 centre (21.2132, -21.2132) radius 0.5
extrude "Extrude3''''''''''''" cut sketch "Sketch3 (13)" along normal blind 5.2 from surface at 20.2 bodies 17 in component "Prop_RR"
sketch "Sketch1 (18)" plane through (0, 0, 0) normal (0, 0, 1) x (1, 0, 0) in component "Cover"
  line L0 (-13.7, -12.7) -> (13.9, -12.7)
  line L1 (13.9, -12.7) -> (13.9, 12.7)
  line L2 (13.9, 12.7) -> (-13.7, 12.7)
  line L3 (-13.7, 12.7) -> (-13.7, -12.7)
extrude "Extrude1'''''''''''''''''" add sketch "Sketch1 (18)" along normal blind 1 from surface at 18.3 separate body makes body 18 in component "Cover"
sketch "Sketch2 (18)" plane through (0, 0, 0) normal (0, 0, 1) x (1, 0, 0) in component "Cover"
  line L0 (-13.7, -9.5) -> (-12.7, -9.5)
  line L1 (-12.7, -9.5) -> (-12.7, 9.5)
  line L2 (-12.7, 9.5) -> (-13.7, 9.5)
  line L3 (-13.7, 9.5) -> (-13.7, -9.5)
extrude "Extrude2'''''''''''''''''" add sketch "Sketch2 (18)" along normal blind 16.3 from surface at 2.1 bodies 18 in component "Cover"
sketch "Sketch3 (14)" plane through (0, 0, 0) normal (0, 0, 1) x (1, 0, 0) in component "Cover"
  line L0 (-2.5, -12.7) -> (2.5, -12.7)
  line L1 (2.5, -12.7) -> (2.5, -11.9)
  line L2 (2.5, -11.9) -> (-2.5, -11.9)
  line L3 (-2.5, -11.9) -> (-2.5, -12.7)
extrude "Extrude3'''''''''''''" add sketch "Sketch3 (14)" along normal blind 6.1 from surface at 12.3 bodies 18 in component "Cover"
sketch "Sketch4 (10)" plane through (0, 0, 0) normal (0, 0, 1) x (1, 0, 0) in component "Cover"
  line L0 (-2, -11.9) -> (2, -11.9)
  line L1 (2, -11.9) -> (2, -11.3)
  line L2 (2, -11.3) -> (-2, -11.3)
  line L3 (-2, -11.3) -> (-2, -11.9)
extrude "Extrude4'''''''''" add sketch "Sketch4 (10)" along normal blind 0.8 from surface at 13.4 bodies 18 in component "Cover"